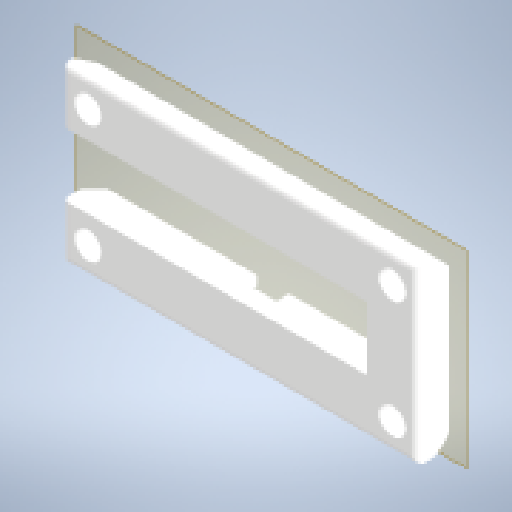
# Autodesk Inventor part: крепление ушей часть 2
Saved by Autodesk Inventor 2024.2 (Build 282272000, 272)
## iProperties
Created: 2026-10-18
Part Number: крепление ушей часть 2
Material: PLA
Document SubType Name: Modeling
Designer: katya_notebook
Density: 1.24 g/cm^3
Appearance: Типовые
Author: katya_notebook
Autodesk Inventor part; units mm, degrees
ref_plane "YZ Plane" through (0, 0, 0) normal (1, 0, 0) x (0, 1, 0)
ref_plane "XZ Plane" through (0, 0, 0) normal (0, 1, 0) x (-1, 0, 0)
ref_plane "XY Plane" through (0, 0, 0) normal (0, 0, 1) x (1, 0, 0)
ref_plane "РабПлоскость1" through (0, 0, 0) normal (0, 0, 1) x (1, 0, 0)
sketch "Эскиз1" plane through (0, 0, 0) normal (0, 0, 1) x (1, 0, 0)
  circle A0 centre (51.85, -22.75) radius 2.1
  circle A1 centre (3.95, -22.75) radius 2.1
  circle A2 centre (51.85, -4.25) radius 2.1
  circle A3 centre (3.95, -4.25) radius 2.1
  line L0 (25.6025, -23.25) -> (25.6025, -24.8476)
  line L1 (25.6025, -24.8476) -> (30.6025, -24.8476)
  line L2 (30.6025, -24.8476) -> (30.6025, -23.25)
  line L3 (30.6025, -23.25) -> (31.9975, -23.25)
  line L4 (31.9975, -23.25) -> (31.9975, -20)
  line L5 (31.9975, -20) -> (30.6025, -20)
  line L6 (30.6025, -20) -> (30.6025, -18.5)
  line L7 (30.6025, -18.5) -> (47.9, -18.5)
  line L8 (47.9, -18.5) -> (47.9, -8.5)
  line L9 (47.9, -8.5) -> (30.6025, -8.5)
  line L10 (30.6025, -8.5) -> (30.6025, -7)
  line L11 (30.6025, -7) -> (31.9975, -7)
  line L12 (31.9975, -7) -> (31.9975, -3.75)
  line L13 (31.9975, -3.75) -> (30.6025, -3.75)
  line L14 (30.6025, -3.75) -> (30.6025, -2.1524)
  line L15 (30.6025, -2.1524) -> (25.6025, -2.1524)
  line L16 (25.6025, -2.1524) -> (25.6025, -3.75)
  line L17 (25.6025, -3.75) -> (24.2075, -3.75)
  line L18 (24.2075, -3.75) -> (24.2075, -7)
  line L19 (24.2075, -7) -> (25.6025, -7)
  line L20 (25.6025, -7) -> (25.6025, -8.5)
  line L21 (25.6025, -8.5) -> (7.9, -8.5)
  line L22 (7.9, -8.5) -> (7.9, -18.5)
  line L23 (7.9, -18.5) -> (25.6025, -18.5)
  line L24 (25.6025, -18.5) -> (25.6025, -20)
  line L25 (25.6025, -20) -> (24.2075, -20)
  line L26 (24.2075, -20) -> (24.2075, -23.25)
  line L27 (24.2075, -23.25) -> (25.6025, -23.25)
  line L28 (0, 0) -> (55.8, 0)
  line L29 (55.8, 0) -> (55.8, -27)
  line L30 (55.8, -27) -> (0, -27)
  line L31 (0, -27) -> (0, 0)
  line L32 (24.2075, -7) -> (31.9975, -7)
  line L33 (31.9975, -7) -> (31.9975, -3.75)
  line L34 (31.9975, -3.75) -> (24.2075, -3.75)
  line L35 (24.2075, -3.75) -> (24.2075, -7)
  line L36 (24.2075, -23.25) -> (31.9975, -23.25)
  line L37 (31.9975, -23.25) -> (31.9975, -20)
  line L38 (31.9975, -20) -> (24.2075, -20)
  line L39 (24.2075, -20) -> (24.2075, -23.25)
  constraints: 80 end point, 18 horizontal, 16 vertical, 4 centre point, 4 parallel, 2 perpendicular, 39 other
extrude "Выдавливание1" add sketch "Эскиз1" along normal blind 5
sketch "Эскиз2" plane through (0, 0, 5) normal (0, 0, 1) x (1, 0, 0)
  line L0 (30.6025, -7) -> (30.6025, -8.5) projected
  line L1 (31.9975, -7) -> (30.6025, -7) projected
  line L2 (24.2075, -7) -> (24.2075, -3.75) projected
  line L3 (31.9975, -7) -> (24.2075, -7)
  line L4 (24.2075, -7) -> (24.2075, -3.75)
  line L5 (24.2075, -3.75) -> (31.9975, -3.75)
  line L6 (31.9975, -3.75) -> (31.9975, -7)
  line L7 (31.9975, -20) -> (31.9975, -23.25) projected
  line L8 (24.2075, -23.25) -> (24.2075, -20) projected
  line L9 (31.9975, -23.25) -> (24.2075, -23.25)
  line L10 (24.2075, -23.25) -> (24.2075, -20)
  line L11 (24.2075, -20) -> (31.9975, -20)
  line L12 (31.9975, -20) -> (31.9975, -23.25)
  point P0 (0, 0)
  constraints: 16 end point, 4 parallel, 2 horizontal, 2 perpendicular
extrude "Выдавливание2" add sketch "Эскиз2" against normal blind 1.5
sketch "Эскиз3" plane through (0, 0, 5) normal (0, 0, 1) x (1, 0, 0)
  line L0 (25.6025, -23.25) -> (30.6025, -23.25) projected
  line L1 (25.6025, -24.8476) -> (25.6025, -23.25) projected
  line L2 (30.6025, -24.8476) -> (25.6025, -24.8476) projected
  line L3 (30.6025, -23.25) -> (30.6025, -24.8476) projected
  line L4 (30.6025, -20) -> (25.6025, -20) projected
  line L5 (30.6025, -18.5) -> (30.6025, -20) projected
  line L6 (25.6025, -20) -> (25.6025, -18.5) projected
  line L7 (30.6025, -7) -> (30.6025, -8.5) projected
  line L8 (25.6025, -7) -> (30.6025, -7) projected
  line L9 (25.6025, -8.5) -> (25.6025, -7) projected
  line L10 (30.6025, -3.75) -> (25.6025, -3.75) projected
  line L11 (30.6025, -2.1524) -> (30.6025, -3.75) projected
  line L12 (25.6025, -2.1524) -> (30.6025, -2.1524) projected
  line L13 (25.6025, -3.75) -> (25.6025, -2.1524) projected
  line L14 (30.6025, -8.5) -> (25.6025, -8.5) projected
  line L15 (25.6025, -18.5) -> (30.6025, -18.5) projected
  point P0 (0, 0)
extrude "Выдавливание3" add sketch "Эскиз3" against normal blind 3
fillet "Сопряжение1" radius 1 4 edges at (27.9, 0, 5) (55.8, -13.5, 5) (27.9, -27, 5) (0, -13.5, 5)
sketch "Эскиз4" plane through (0, 0, 5) normal (0, 0, 1) x (1, 0, 0)
  line L0 (7.9, -18.5) -> (-1.0047, -18.5)
  line L1 (-1.0047, -18.5) -> (-1.0047, -8.5)
  line L2 (-1.0047, -8.5) -> (7.9, -8.5)
  line L3 (7.9, -8.5) -> (7.9, -18.5)
  point P0 (0, 0)
  constraints: 8 end point, 2 parallel, 1 horizontal, 1 perpendicular
extrude "Выдавливание4" cut sketch "Эскиз4" against normal blind 10
chamfer "Фаска1" distance 2.1 angle 45 2 edges at (0, -4.25, 0) (27.9, 0, 0)
chamfer "Фаска2" distance 2.1 angle 45 1 edges at (1.05, -1.05, 1.05)
chamfer "Фаска3" distance 2.1 angle 45 2 edges at (0, -22.75, 0) (27.9, -27, 0)
chamfer "Фаска4" distance 2.1 angle 45 1 edges at (1.05, -25.95, 1.05)
